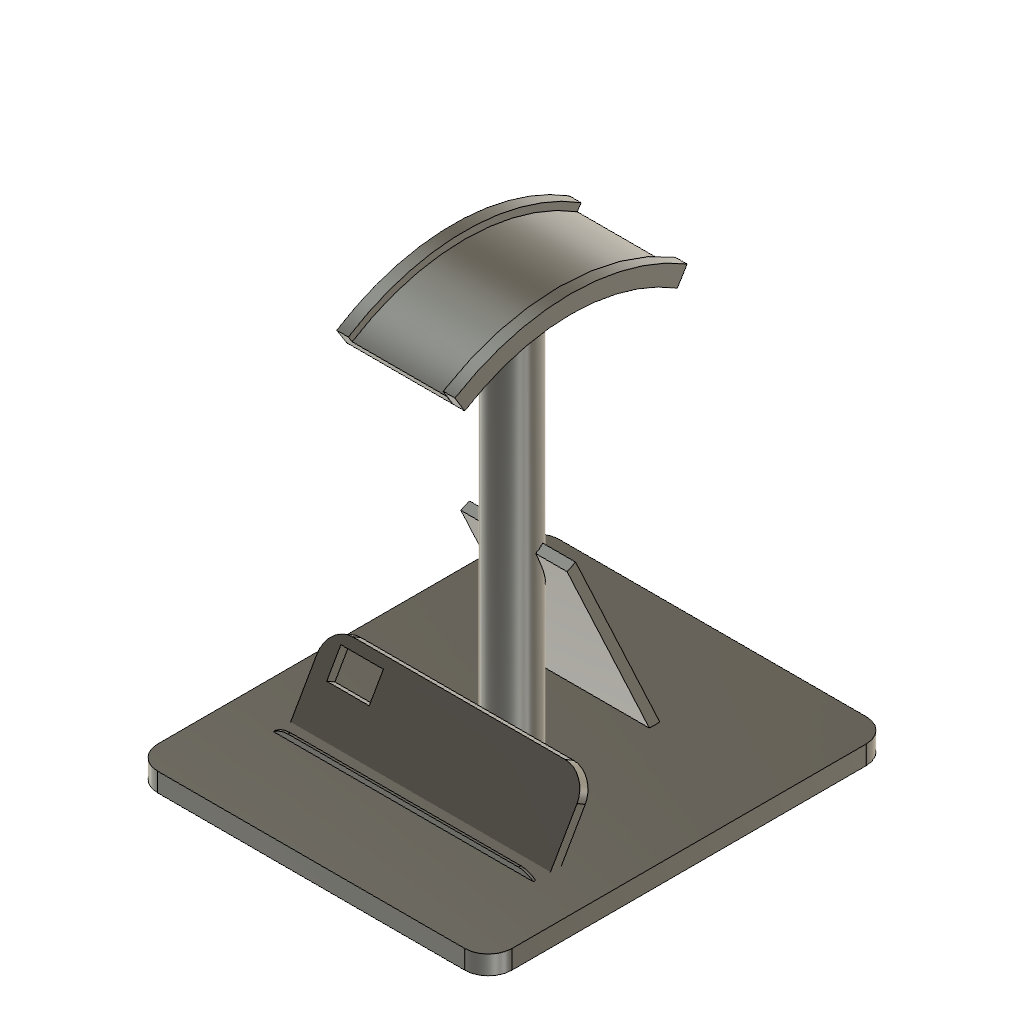
Basic Headphone Stand (Autodesk Fusion 360 design; units mm, degrees)
part number: 2026-09-23-17-07-22-350
Autodesk Fusion 360 part; units mm, degrees
sketch "Sketch4" plane through (0, 0, 0) normal (0, 0, 1) x (1, 0, 0)
  line L0 (75, -85) -> (-75, -85)
  line L1 (-75, -85) -> (-75, 85)
  line L2 (-75, 85) -> (75, 85)
  line L3 (75, 85) -> (75, -85)
  constraint horizontal L0
  constraint vertical L1
  constraint horizontal L2
  constraint vertical L3
extrude "Extrude3" add sketch "Sketch4" along normal blind 8 makes body 1
fillet "Fillet5" radius 10 4 edges at (75, 85, 4) (-75, 85, 4) (75, -85, 4) (-75, -85, 4) on bodies 1
sketch "Sketch5" plane through (0, 0, 8) normal (0, 0, 1) x (-1, 0, 0)
  arc A0 (75, 75) -> (65, 85) centre (65, 75) ccw
  line L0 (65, 85) -> (-65, 85)
  arc A1 (-65, 85) -> (-75, 75) centre (-65, 75) ccw
  line L1 (-75, 75) -> (-75, -75)
  arc A2 (-75, -75) -> (-65, -85) centre (-65, -75) ccw
  line L2 (-65, -85) -> (65, -85)
  arc A3 (65, -85) -> (75, -75) centre (65, -75) ccw
  line L3 (75, -75) -> (75, 75)
  circle A4 centre (0, 0) radius 10
  dimension "d17" = 20
  constraint coincident A4.centre origin
  measures "d17" diameter of A4
extrude "Extrude4" add sketch "Sketch5" along normal blind 170 contours A4 bodies 1
sketch "Sketch10" plane through (0, 0, 0) normal (1, 0, 0) x (0, 1, 0)
  line L0 (10, 178) -> (-10, 178)
  arc A0 (45, 165) -> (-45, 165) centre (0, 93.6154) ccw
  arc A1 (47.6664, 169.2297) -> (-47.6664, 169.2297) centre (0, 93.6154) ccw
  line L1 (-47.6664, 169.2297) -> (-45, 165)
  line L2 (47.6664, 169.2297) -> (45, 165)
  dimension "d32" = 5
  constraint tangent L0 A0
  constraint perpendicular A0 L1
  constraint perpendicular A0 L2
extrude "Extrude8" cut sketch "Sketch10" along normal mid plane 60 bodies 1
extrude "Extrude9" add sketch "Sketch10" along normal blind 20 and the other way blind 20 bodies 1
sketch "Sketch11" plane through (20, 0, 0) normal (1, 0, 0) x (0, 1, 0)
  line L0 (-47.6664, 169.2297) -> (-45, 165)
  arc A0 (45, 165) -> (-45, 165) centre (0, 93.6154) ccw
  line L1 (45, 165) -> (47.6664, 169.2297)
  arc A1 (47.6664, 169.2297) -> (-47.6664, 169.2297) centre (0, 93.6154) ccw
  arc A2 (45, 165) -> (-45, 165) centre (0, 90.9132) ccw
  arc A3 (49.1531, 171.8375) -> (-49.1531, 171.8375) centre (0, 90.9132) ccw
  line L2 (49.1531, 171.8375) -> (45, 165)
  line L3 (-49.1531, 171.8375) -> (-45, 165)
  dimension "d39" = 8
  constraint tangent A1 A2
  constraint coincident A0.start L1.start
  constraint coincident L0.end A0.end
  constraint perpendicular A2 L3
extrude "Extrude10" add sketch "Sketch11" along normal blind 5 contours A0 A1 L2 L3 | A1 A3 L2 L3 bodies 1
sketch "Sketch12" plane through (-20, 0, 0) normal (-1, 0, 0) x (0, -1, 0)
  line L0 (45, 165) -> (47.6664, 169.2297)
  arc A0 (47.6664, 169.2297) -> (-47.6664, 169.2297) centre (0, 93.6154) ccw
  line L1 (-47.6664, 169.2297) -> (-45, 165)
  arc A1 (45, 165) -> (-45, 165) centre (0, 93.6154) ccw
  arc A2 (45, 165) -> (-45, 165) centre (0, 93.6154) ccw
  arc A3 (49.2662, 171.7675) -> (-49.2662, 171.7675) centre (0, 93.6154) ccw
  line L2 (49.2662, 171.7675) -> (45, 165)
  line L3 (-49.2662, 171.7675) -> (-45, 165)
  dimension "d42" = 8
  constraint coincident L0.start A1.start
  constraint coincident L1.end A1.end
  constraint perpendicular A2 L2
  constraint perpendicular A1 L3
extrude "Extrude11" add sketch "Sketch12" along normal blind 5 bodies 1
sketch "Sketch13" plane through (0, 0, 0) normal (1, 0, 0) x (0, 1, 0)
  line L0 (-39.9641, 5.6891) -> (-22.4641, 36)
  line L1 (-39.9641, 5.6891) -> (-21, 5.6891) construction
  line L2 (-22.4641, 36) -> (-19, 34)
  line L3 (-19, 34) -> (-36.5, 3.6891)
  line L4 (-36.5, 3.6891) -> (-39.9641, 5.6891)
  dimension "d45" = 60
  dimension "d46" = 35
  dimension "d47" = 4
  dimension "d48" = 35
  constraint horizontal L1
  constraint perpendicular L0 L2
  constraint perpendicular L2 L3
  measures "d45" angle of L0 L1
  measures "d46" distance of L0.start L0.end
  measures "d47" distance of L0.end L2.end
  measures "d48" distance of L2.end L3.end
extrude "Extrude12" add sketch "Sketch13" along normal mid plane 110 separate body makes body 2
sketch "Sketch14" plane through (0, 0, 8) normal (0, 0, 1) x (-1, 0, 0)
  circle A0 centre (0, 0) radius 10
  arc A1 (75, 75) -> (65, 85) centre (65, 75) ccw
  line L0 (65, 85) -> (-65, 85)
  arc A2 (-65, 85) -> (-75, 75) centre (-65, 75) ccw
  line L1 (-75, 75) -> (-75, -75)
  arc A3 (-75, -75) -> (-65, -85) centre (-65, -75) ccw
  line L2 (-65, -85) -> (65, -85)
  arc A4 (65, -85) -> (75, -75) centre (65, -75) ccw
  line L3 (75, -75) -> (75, 75)
  line L4 (-55, 45) -> (55, 45)
  line L5 (55, 45) -> (55, 46)
  line L6 (55, 46) -> (-55, 46)
  line L7 (-55, 46) -> (-55, 45)
  constraint horizontal L4
  constraint perpendicular L4 L5
  constraint perpendicular L5 L6
  constraint perpendicular L4 L7
extrude "Extrude13" add sketch "Sketch14" along normal blind 1.2 contours L4 L5 L6 L7 bodies 1
fillet "Fillet6" radius 10 2 edges at (55, -20.7321, 35) (-55, -20.7321, 35) on bodies 2
extrude "Extrude14" add 1 faces at (18.3333, -45.3333, 9.2) along direction (0, 0, 1) blind 1 on bodies 1 bodies 1
fillet "Fillet7" radius 10 2 edges at (55, -45.5, 10.2) (-55, -45.5, 10.2) on bodies 1
sketch "Sketch15" plane through (0, -32.4365, 18.7272) normal (0, -0.866025, 0.5) x (1, 0, 0)
  arc A0 (-45, 19.9449) -> (-55, 9.9449) centre (-45, 9.9449) ccw
  line L0 (-55, 9.9449) -> (-55, -15.0551)
  line L1 (-55, -15.0551) -> (55, -15.0551)
  line L2 (55, -15.0551) -> (55, 9.9449)
  arc A1 (55, 9.9449) -> (45, 19.9449) centre (45, 9.9449) ccw
  line L3 (45, 19.9449) -> (-45, 19.9449)
  line L4 (-48, 16) -> (-30, 16)
  line L5 (-30, 16) -> (-30, 4)
  line L6 (-30, 4) -> (-48, 4)
  line L7 (-48, 4) -> (-48, 16)
  constraint horizontal L4
  constraint perpendicular L4 L5
  constraint perpendicular L5 L6
  constraint perpendicular L4 L7
extrude "Extrude15" cut sketch "Sketch15" along normal mid plane 8 contours L4 L5 L6 L7 bodies 2
sketch "Sketch16" plane through (0, 0, 0) normal (0, 1, 0) x (1, 0, 0)
  line L0 (24.9561, -7.906) -> (-13.0795, -89.4737)
  line L1 (24.9561, -7.906) -> (114.9561, -7.906) construction
  line L2 (-13.0795, -89.4737) -> (-16.7047, -87.7833)
  line L3 (-16.7047, -87.7833) -> (21.3309, -6.2156)
  line L4 (21.3309, -6.2156) -> (24.9561, -7.906)
  dimension "d61" = 115
  dimension "d62" = 90
  dimension "d63" = 4
  dimension "d64" = 90
  constraint perpendicular L0 L2
  constraint perpendicular L2 L3
  measures "d61" angle of L0 L1
  measures "d62" distance of L0.start L0.end
  measures "d63" distance of L0.end L2.end
  measures "d64" distance of L2.end L3.end
extrude "Extrude16" add sketch "Sketch16" along normal blind 5 separate body makes body 3
move_body "Move1" bodies 3 to x (0, 1, 0) y (-1, 0, 0) z (0, 0, 1) at (-16.7047, 16.7047, -5)
extrude "Extrude17" add 1 faces at (-16.7047, 26.5655, 28.9683) along direction (1, 0, 0) blind 40 on bodies 3 bodies 1 2 3
